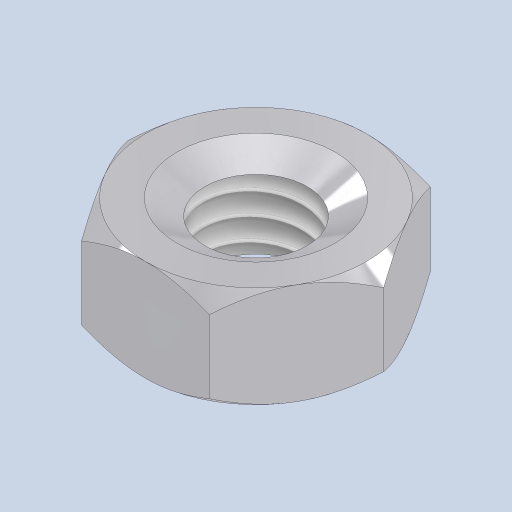
# Autodesk Inventor part: Porca sextavada DIN 934 M4
Saved by Autodesk Inventor 2024.3 (Build 283343000, 343)
## iProperties
Created: 2025-02-01
Part Number: Porca sextavada DIN 934 M4
Material: Aço inoxidável
Document SubType Name: Modeling
Designer: Cliente
Density: 8 g/cm^3
Appearance: Inoxidável - Escovado
Mass: 0.823522 g
Surface Area: 1.66619 cm^2
Volume: 0.10294 cm^3
Author: Cliente
Autodesk Inventor part; units mm, degrees
ref_plane "YZ Plane" through (0, 0, 0) normal (1, 0, 0) x (0, 1, 0)
ref_plane "XZ Plane" through (0, 0, 0) normal (0, 1, 0) x (-1, 0, 0)
sketch "Esboço1" plane through (0, 0, 0) normal (0, 1, 0) x (-1, 0, 0)
  line L0 (-4.0415, 0) -> (-2.0207, 3.5)
  line L1 (-2.0207, 3.5) -> (2.0207, 3.5)
  line L2 (2.0207, 3.5) -> (4.0415, 0)
  line L3 (4.0415, 0) -> (2.0207, -3.5)
  line L4 (2.0207, -3.5) -> (-2.0207, -3.5)
  line L5 (-2.0207, -3.5) -> (-4.0415, 0)
  point P0 (0, 0)
  point P1 (0, 0)
  dimension "d1" = 7
  constraints: 12 end point, 1 coincident, 1 horizontal alignment, 13 other
  measures "d1" distance between parallel lines of L1 L4
extrude "Extrusão1" add sketch "Esboço1" along normal mid plane 3.2
sketch "Esboço2" plane through (0, 1.6, 0) normal (0, 1, 0) x (1, 0, 0)
  point P0 (0, 0)
hole "Furo1" at (0, 1.6, 0) direction (0, -1, 0) diameter 3.242 end through all countersink diameter 5 countersink angle 120 thread size "M4x0.7" class "6H" standard "ANSI Metric M Profile"
sketch "Esboço3" plane through (0, 0, 0) normal (1, 0, 0) x (0, 1, 0)
  line L0 (-1.6, 0) -> (1.6, 0) projected
  line L1 (0, 0) -> (-1.6, 0)
  line L2 (-1.6, 0) -> (-1.6, 2.5)
  line L3 (-1.6, 3.5) -> (-1.6, 0) projected
  line L4 (-1.6, 2.5) -> (-1.0925, 1.621)
  line L5 (-1.6, 1.621) -> (1.0925, 1.621) projected
  line L6 (-1.6, 2.5) -> (-0.585, 2.5) construction
  line L7 (-1.0925, 1.621) -> (-1.0925, 0)
  point P0 (-1.0925, 0)
  dimension "d11" = 2.5
  dimension "d12" = 60
  constraints: 10 end point, 3 point on line, 2 horizontal, 1 equal length, 1 perpendicular
  measures "d11" distance of L0.start L2.end
  measures "d12" angle of L4 L6
revolve "Revolução1" cut sketch "Esboço3" angle 360 about axis through (0, -1.6, 0) along (0, 1, 0)
ref_plane "Plano de trabalho1" through (2.0207, 0, 3.5) normal (-0.8660254, 0, 0.5) x (0, 1, 0)
sketch "Esboço4" plane through (2.0207, 0, 3.5) normal (-0.8660254, 0, 0.5) x (0, 1, 0)
  line L0 (0, 4.0415) -> (1.6, 4.0415)
  line L1 (1.6, 6.0622) -> (1.6, 2.0207) projected
  line L2 (1.6, 0.5415) -> (1.6, 7.5415)
  line L3 (1.6, 0.5415) -> (1.15, 0)
  line L4 (-1.6, 0) -> (1.6, 0) projected
  line L5 (1.6, 2.0207) -> (1.6, 0) projected
  line L6 (-1.6, 2.0207) -> (1.6, 2.0207) projected
  line L7 (-1.6, 0) -> (-1.6, 2.0207) projected
  line L8 (-1.6, 0.5415) -> (-1.15, 0)
  line L9 (1.6, 0.5415) -> (-1.6, 0.5415)
  line L10 (1.15, 0) -> (-1.15, 0)
  point P0 (1.3075, 0)
  point P1 (0, 0)
  dimension "d14" = 7
  dimension "d18" = 2.3
  constraints: 12 end point, 4 midpoint, 3 point on line, 2 horizontal, 1 vertical
  measures "d14" distance of L2.start L2.end
  measures "d18" distance of L3.end L8.end
revolve "Revolução2" cut sketch "Esboço4" angle 360 about axis through (0, 0, 0) along (0, 1, 0) contours L5 L4 L3 | L8 L4 L7
